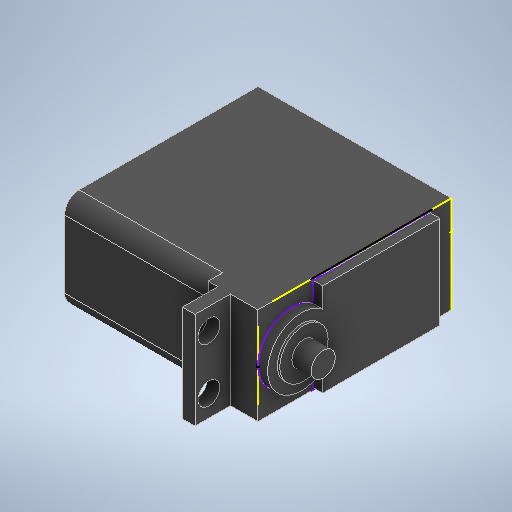
# Autodesk Inventor part: SERVOMOTOR
Saved by Autodesk Inventor 2025.3 (Build 293356000, 356)
## iProperties
Created: 2026-10-05
Part Number: SERVOMOTOR
Material: PLA (Impresión 3D)
Document SubType Name: Modeling
Designer: ASUS
Density: 1.24 g/cm^3
Appearance: Genérico
Mass: 41.6962 g
Surface Area: 70.142 cm^2
Volume: 33.626 cm^3
Author: ASUS
Autodesk Inventor part; units mm, degrees
ref_plane "YZ Plane" through (0, 0, 0) normal (1, 0, 0) x (0, 1, 0)
ref_plane "XZ Plane" through (0, 0, 0) normal (0, 1, 0) x (-1, 0, 0)
ref_plane "XY Plane" through (0, 0, 0) normal (0, 0, 1) x (1, 0, 0)
sketch "Boceto1" plane through (0, 0, 0) normal (0, 0, 1) x (1, 0, 0)
  line L0 (-5.0338, 5.8765) -> (34.9662, 5.8765)
  line L1 (34.9662, 5.8765) -> (34.9662, -14.1235)
  line L2 (34.9662, -14.1235) -> (-5.0338, -14.1235)
  line L3 (-5.0338, -14.1235) -> (-5.0338, 5.8765)
  point P0 (0, 0)
  dimension "d0" = 40
  dimension "d1" = 20
  constraints: 8 end point, 2 parallel, 1 horizontal, 1 perpendicular
  measures "d0" distance of L1.end L2.end
  measures "d1" distance of L0.end L1.end
extrude "Extrusión1" add sketch "Boceto1" along normal blind 40
fillet "Empalme1" radius 3 1 edges at (14.9662, 5.8765, 40)
fillet "Empalme2" radius 3 1 edges at (14.9662, -14.1235, 40)
sketch "Boceto2" plane through (34.9662, -14.1235, 0) normal (1, 0, 0) x (0, 0, -1)
  line L0 (0, 20) -> (-37, 20) projected
  line L1 (-4, 20) -> (-29, 20)
  line L2 (-29, 0) -> (-4, 0)
  line L3 (0, 0) -> (0, 20) projected
  circle A0 centre (-33, 10) radius 7
  line L4 (-40, 3) -> (-40, 17) projected
  line L5 (-28.6, 0.4) -> (-28.6, 19.6)
  line L6 (-28.6, 19.6) -> (-4.4, 19.6)
  line L7 (-4.4, 19.6) -> (-4.4, 0.4)
  line L8 (-4.4, 0.4) -> (-28.6, 0.4)
  point P0 (0, 14.1235)
  point P1 (-40, 10)
  point P2 (-28.6, 15.4443)
  point P3 (-28.6, 4.5557)
  dimension "d6" = 25
  dimension "d7" = 20
  dimension "d9" = 14
  dimension "d10" = 7
  constraints: 12 end point, 3 parallel, 1 centre point, 1 horizontal, 1 midpoint, 1 perpendicular, 1 point on line
  measures "d6" distance of L2.end L2.start
  measures "d7" distance of L2.start L1.end
  measures "d9" diameter of A0
  measures "d10" distance of point (-40, 10) A0.centre
extrude "Extrusión3" add sketch "Boceto2" along normal blind 2 contours A0 L5 | L5 A0
extrude "Extrusión4" add sketch "Boceto2" along normal blind 2 contours A0 L5 L6 L7 L8
sketch "Boceto3" plane through (36.9662, -14.1235, 0) normal (1, 0, 0) x (0, 0, -1)
  arc A0 (-37, 20) -> (-40, 17) centre (-37, 17) ccw projected
  line L0 (-40, 17) -> (-40, 20)
  line L1 (-40, 20) -> (-47.32, 20)
  arc A1 (-40, 3) -> (-37, 0) centre (-37, 3) ccw projected
  line L2 (-37, 0) -> (-47.32, 0)
  line L3 (-47.32, 0) -> (-47.32, 20)
  line L4 (-37, 20) -> (-40, 20)
  circle A2 centre (-44.42, 15.6) radius 2.25
  circle A3 centre (-44.42, 4.4) radius 2.25
  line L5 (-40, 3) -> (-40, 17)
  line L6 (-40, 0) -> (-40, 3)
  point P0 (0, 14.1235)
  dimension "d49" = 7.32
  dimension "d50" = 4.5
  dimension "d51" = 4.4
  dimension "d52" = 2.9
  dimension "d54" = 4.4
  constraints: 14 end point, 3 perpendicular, 3 tangent, 2 centre point, 2 point on line, 1 collinear, 1 horizontal, 1 vertical
  measures "d49" distance of L0.end L1.end
  measures "d50" diameter of A2
  measures "d51" distance from line of L1 A2.centre
  measures "d52" distance from line of L3 A2.centre
  measures "d54" distance from line of L2 A3.centre
sketch "Boceto4" plane through (36.9662, -14.1235, 0) normal (1, 0, 0) x (0, 0, -1)
  arc A0 (-28.6, 15.4443) -> (-40, 10) centre (-33, 10) ccw projected
  circle A1 centre (-33, 10) radius 5
  point P0 (0, 14.1235)
  dimension "d18" = 10
  constraints: 1 centre point, 1 coincident
  measures "d18" diameter of A1
extrude "Extrusión5" add sketch "Boceto4" along normal blind 0.5
sketch "Boceto5" plane through (37.4662, -4.1235, 33) normal (1, 0, 0) x (0, 0, -1)
  circle A0 centre (0, 0) radius 5 projected
  circle A1 centre (0, 0) radius 2.5
  point P0 (33, 4.1235)
  dimension "d21" = 5
  constraints: 1 centre point, 1 coincident
  measures "d21" diameter of A1
extrude "Extrusión6" add sketch "Boceto5" along normal blind 4 contours A1
sketch "Boceto13" plane through (-5.0338, -14.1235, 0) normal (0, -1, 0) x (1, 0, 0)
  circle A0 centre (6.9976, 30.0772) radius 4.5
  point P0 (5.0338, 0)
  dimension "d45" = 9
  constraints: 1 centre point
  measures "d45" diameter of A0
extrude "Extrusión13" add sketch "Boceto13" along normal blind 2
extrude "Extrusión14" add sketch "Boceto3" against normal blind 10.3 contours L5 L6 L2 L3 L1 L0
sketch "Boceto14" plane through (36.9662, -14.1235, 0) normal (1, 0, 0) x (0, 0, -1)
  line L0 (-47.32, 20) -> (-40, 20) projected
  line L1 (-40, 20) -> (-47.32, 20)
  line L2 (-47.32, 20) -> (-47.32, 0)
  line L3 (-40, 0.0076) -> (-40, 20)
  circle A0 centre (-44.42, 15.6) radius 2.25 projected
  circle A1 centre (-44.42, 15.6) radius 2.25
  circle A2 centre (-44.42, 4.4) radius 2.25 projected
  circle A3 centre (-44.42, 4.4) radius 2.25
  line L4 (-40, 0) -> (-47.32, 0) projected
  line L5 (-47.32, 0) -> (-40, 0)
  line L6 (-40, 20) -> (-47.32, 20)
  line L7 (-47.32, 0) -> (-40, 0)
  line L8 (-40, 20) -> (-40, 0)
  circle A4 centre (-44.42, 15.6) radius 2.25
  circle A5 centre (-44.42, 4.4) radius 2.25
  point P0 (0, 14.1235)
  constraints: 14 end point, 4 centre point, 4 coincident, 4 collinear, 2 concentric, 1 parallel, 1 perpendicular
extrude "Extrusión15" cut sketch "Boceto14" against normal blind 7.7
sketch "Boceto15" plane through (34.9662, -14.1235, 0) normal (1, 0, 0) x (0, 0, -1)
  line L0 (0, 20) -> (-37, 20) projected
  line L1 (-40, 20) -> (-40, 17) projected
  line L2 (-37, 20) -> (-40, 20)
  line L3 (-40, 20) -> (-40, 17)
  arc A0 (-40, 3) -> (-37, 0) centre (-37, 3) ccw projected
  line L4 (-37, 0) -> (-40, 0)
  line L5 (-40, 0) -> (-40, 3)
  circle A1 centre (-37, 3) radius 3
  arc A2 (-37, 20) -> (-40, 17) centre (-37, 17) ccw projected
  circle A3 centre (-37, 17) radius 3
  point P0 (0, 14.1235)
  constraints: 8 end point, 2 centre point, 2 coincident, 2 horizontal, 2 tangent, 1 collinear, 1 perpendicular
extrude "Extrusión16" add sketch "Boceto15" against normal blind 10.3 contours L2 A2 L1 | A0 L4 L5
